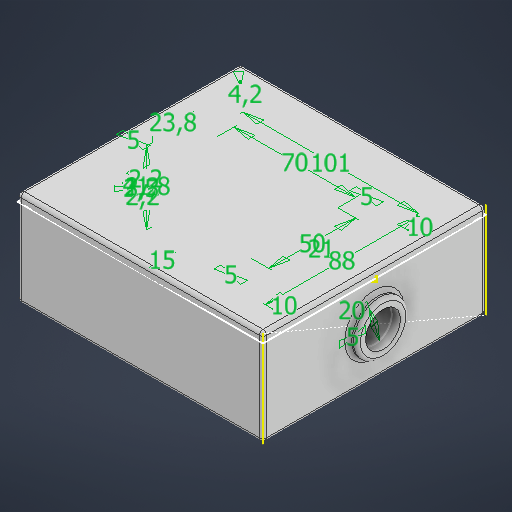
# Autodesk Inventor part: CaseBitDogLabV3
Saved by Autodesk Inventor 2027 (Build 310192000, 192)
## iProperties
Created: 2026-10-26
Part Number: CaseBitDogLabV3
Material: Genérico
Document SubType Name: Modeling
Designer: EspacoMaker
Density: 1 g/cm^3
Appearance: Padrão
Author: EspacoMaker
Autodesk Inventor part; units mm, degrees
ref_plane "YZ Plane" through (0, 0, 0) normal (1, 0, 0) x (0, 1, 0)
ref_plane "XZ Plane" through (0, 0, 0) normal (0, 1, 0) x (-1, 0, 0)
ref_plane "XY Plane" through (0, 0, 0) normal (0, 0, 1) x (1, 0, 0)
sketch "EsboçoBase" plane through (0, 0, 0) normal (0, 1, 0) x (-1, 0, 0)
  line L0 (50.5, 44) -> (-50.5, 44) construction
  line L1 (-50.5, 44) -> (-50.5, -44) construction
  line L2 (-50.5, -44) -> (50.5, -44) construction
  line L3 (50.5, -44) -> (50.5, 44) construction
  line L4 (50.5, 44) -> (-50.5, -44) construction
  line L5 (-50.5, 44) -> (50.5, -44) construction
  line L6 (-65.5, 59) -> (65.5, 59)
  line L7 (65.5, 59) -> (65.5, -59)
  line L8 (65.5, -59) -> (-65.5, -59)
  line L9 (-65.5, -59) -> (-65.5, 59)
  line L10 (50.5, 44) -> (-50.5, 44)
  line L11 (-50.5, 44) -> (-50.5, 34)
  line L12 (-50.5, 34) -> (50.5, 34)
  line L13 (50.5, 34) -> (50.5, 44)
  line L14 (50.5, -44) -> (-50.5, -44)
  line L15 (-50.5, -44) -> (-50.5, -34)
  line L16 (-50.5, -34) -> (50.5, -34)
  line L17 (50.5, -34) -> (50.5, -44)
  line L18 (45.5, 25) -> (-24.5, 25) construction
  line L19 (-24.5, 25) -> (-24.5, -25) construction
  line L20 (-24.5, -25) -> (45.5, -25) construction
  line L21 (45.5, -25) -> (45.5, 25) construction
  line L22 (-29.5, 44) -> (-29.5, -44) construction
  line L23 (45.5, 0) -> (-24.5, 0) construction
  line L24 (65.5, 0) -> (-65.5, 0) construction
  line L25 (50.5, 39) -> (-29.5, 39) construction
  line L26 (10.5, 39) -> (10.5, -44) construction
  line L27 (10.5, 25) -> (10.5, -25) construction
  circle A0 centre (43.3, 22.8) radius 1.1
  circle A1 centre (43.3, 22.8) radius 3.6
  circle A2 centre (43.3, -22.8) radius 1.1
  circle A3 centre (43.3, -22.8) radius 3.6
  line L28 (-24.5, -25) -> (-24.5, 25) construction
  circle A4 centre (-22.3, 22.8) radius 1.1
  circle A5 centre (-22.3, 22.8) radius 3.6
  circle A6 centre (-22.3, -22.8) radius 1.1
  circle A7 centre (-22.3, -22.8) radius 3.6
  line L29 (70.5, -64) -> (70.5, 64)
  line L30 (70.5, 64) -> (-70.5, 64)
  line L31 (-70.5, 64) -> (-70.5, -64)
  line L32 (-70.5, -64) -> (70.5, -64)
  circle A8 centre (65.5, -59) radius 2.1
  circle A9 centre (65.5, -59) radius 5
  circle A10 centre (65.5, 59) radius 2.1
  circle A11 centre (65.5, 59) radius 5
  line L33 (0, -64) -> (0, 64) construction
  circle A12 centre (-65.5, -59) radius 2.1
  circle A13 centre (-65.5, -59) radius 5
  circle A14 centre (-65.5, 59) radius 2.1
  circle A15 centre (-65.5, 59) radius 5
  line L34 (-29.5, -44) -> (-29.5, -34)
  line L35 (-29.5, 34) -> (-29.5, 44)
  line L36 (-24.5, -44) -> (-24.5, -34)
  line L37 (-24.5, 34) -> (-24.5, 44)
  point P0 (0, 0)
  dimension "d0" = 101
  dimension "d1" = 88
  dimension "d2" = 15
  dimension "d3" = 10
  dimension "d4" = 10
  dimension "d6" = 70
  dimension "d7" = 50
  dimension "d8" = 21
  dimension "d9" = 2.2
  dimension "d10" = 2.2
  dimension "d11" = 2.2
  dimension "d12" = 2.5
  dimension "d13" = 5
  dimension "d22" = 4.2
  dimension "d37" = 5
  dimension "d38" = 5
  constraints: 76 end point, 16 centre point, 15 parallel, 12 midpoint, 8 perpendicular, 8 point on line, 6 symmetric about line, 4 horizontal, 3 collinear, 2 coincident, 1 tangent, 18 other
  measures "d0" distance of L2.end L1.end
  measures "d1" distance of L1.end L0.end
  measures "d2" distance between parallel lines of L0 L6
  measures "d3" distance of L11.end L10.end
  measures "d4" distance of L14.end L15.end
  measures "d6" distance of L20.end L19.end
  measures "d7" distance of L19.end L18.end
  measures "d8" distance between parallel lines of L1 L22
  measures "d9" distance from line of A0.centre L21
  measures "d10" distance from line of L18 A0.centre
  measures "d11" diameter of A0
  measures "d12" radial gap between concentric circles of A0 A1
  measures "d13" distance between parallel lines of L7 L29
  measures "d22" diameter of A8
  measures "d37" distance between parallel lines of L34 L36
  measures "d38" distance between parallel lines of L35 L37
extrude "Fundo" add sketch "EsboçoBase" along normal blind 5 contours L9 A14 L6 | L6 A14 L9 | A14 L9 A15 L6 | L6 A15 L9 A14 | A15 L30 A11 L6 | L6 A11 L7 A9 L8 A13 L9 A15 | L9 A13 L31 A15 | A11 L7 A10 L6 | L6 A10 L7 A11 | A15 L31 L30 | A13 L8 A12 L9 | L9 A12 L8 A13 | A10 L7 L6 | L6 L7 A10 | L30 L29 A11 | A11 L29 A9 L7 | A12 L8 L9 | L9 L8 A12 | L8 A9 L32 A13 | A13 L32 L31 | A9 L8 A8 L7 | L7 A8 L8 A9 | L29 L32 A9 | A8 L8 L7 | L7 L8 A8 | L13 L12 L37 L10 | L37 L12 L35 L10 | L35 L12 L11 L10 | L14 L36 L16 L17 | L14 L34 L16 L36 | L14 L15 L16 L34 | A0 | A1 | A2 | A3 | A4 | A5 | A6 | A7
extrude "Paredes" add sketch "EsboçoBase" against normal blind 50 contours L9 A14 L6 | A14 L9 A15 L6 | A15 L30 A11 L6 | L9 A13 L31 A15 | A11 L7 A10 L6 | A15 L31 L30 | L9 A12 L8 A13 | A10 L7 L6 | L30 L29 A11 | A11 L29 A9 L7 | L9 L8 A12 | L8 A9 L32 A13 | A13 L32 L31 | A9 L8 A8 L7 | L29 L32 A9 | A8 L8 L7 picked at (-66.2111, 60.1934) picked at (-68.2722, 61.8946) picked at (61.5085, 59.3709) picked at (-68.2722, -61.8946) picked at (65.5, 60.3898) picked at (-66.2111, -60.1934) picked at (69.4915, -59.3709) picked at (64.1203, -59.1675)
extrude "ApoioBitDog" add sketch "EsboçoBase" against normal blind 35 contours L13 L12 L37 L10 | L37 L12 L35 L10 | L35 L12 L11 L10 | L14 L36 L16 L17 | L14 L34 L16 L36 | L14 L15 L16 L34
extrude "ApoioPCB" add sketch "EsboçoBase" against normal blind 10 contours A1 | A3 | A5 | A7
sketch "Esboço2" plane through (0, -50, 0) normal (0, -1, 0) x (1, 0, 0)
  circle A0 centre (-65.5, -59) radius 5 projected
  circle A1 centre (-65.5, -59) radius 2.1 projected
  circle A2 centre (-65.5, 59) radius 5 projected
  circle A3 centre (-65.5, 59) radius 2.1 projected
  circle A4 centre (65.5, 59) radius 5 projected
  circle A5 centre (65.5, 59) radius 2.1 projected
  circle A6 centre (65.5, -59) radius 5 projected
  circle A7 centre (65.5, -59) radius 2.1 projected
  point P0 (0, 0)
extrude "Extrusão5" add sketch "Esboço2" against normal blind 50 contours A0 | A1 | A2 | A3 | A4 | A5 | A6 | A7
extrude "Extrusão6" cut sketch "Esboço2" against normal blind 30 contours A1 | A3 | A5 | A7
sketch "Esboço3" plane through (70.5, 5, 64) normal (1, 0, 0) x (0, 0, -1)
  line L0 (128, -55) -> (128, 0) projected
  line L1 (0, -55) -> (0, 0) projected
  line L2 (128, -55) -> (0, 0) construction
  circle A0 centre (64, -27.5) radius 10
  circle A1 centre (64, -27.5) radius 15
  point P0 (64, -5)
  dimension "d27" = 20
  dimension "d28" = 5
  constraints: 2 centre point, 2 end point, 1 midpoint
  measures "d27" diameter of A0
  measures "d28" radial gap between concentric circles of A0 A1
extrude "Extrusão7" cut sketch "Esboço3" against normal blind 5 contours A0
extrude "Extrusão8" add sketch "Esboço3" along normal blind 5 and the other way blind 10
fillet "Arredondamento1" radius 2 20 edges at (68, -50, -64) (0, -50, -64) (-68, -50, -64) (-70.5, -50, -61.5) (-70.5, -50, 0) (-70.5, -50, 61.5) (-68, -50, 64) (0, -50, 64) (68, -50, 64) (70.5, -50, -61.5) (70.5, -50, 0) (70.5, -50, 61.5) (70.5, -22.5, 64) (70.5, -22.5, -64) (70.5, 5, 0) (-70.5, -22.5, -64) (0, 5, -64) (0, 5, 64) (-70.5, -22.5, 64) (-70.5, 5, 0)
fillet "Arredondamento2" radius 2 16 edges at (0, 0, -59) (-61.9645, 0, -55.4645) (-65.5, 0, 0) (0, 0, 59) (-61.9645, 0, 55.4645) (61.9645, 0, 55.4645) (65.5, 0, 0) (61.9645, 0, -55.4645) (25.9, 0, -22.8) (25.9, 0, 22.8) (-39.7, 0, -22.8) (-39.7, 0, 22.8) (70.5, -22.5, 15) (75.5, -22.5, 15) (65.5, -22.5, 15) (60.5, -22.5, 15)
sketch "Esboço4" plane through (-65.5, -50, 54) normal (1, 0, 0) x (0, 0, -1)
  line L0 (86.156, 3.899) -> (62.356, 3.899)
  line L1 (62.356, 3.899) -> (62.356, 45.699)
  line L2 (62.356, 45.699) -> (86.156, 45.699)
  line L3 (86.156, 45.699) -> (86.156, 3.899)
  point P0 (54, 50)
  dimension "d39" = 23.8
  dimension "d40" = 41.8
  constraints: 8 end point, 2 parallel, 1 horizontal, 1 perpendicular
  measures "d39" distance of L1.end L2.end
  measures "d40" distance of L0.end L1.end
